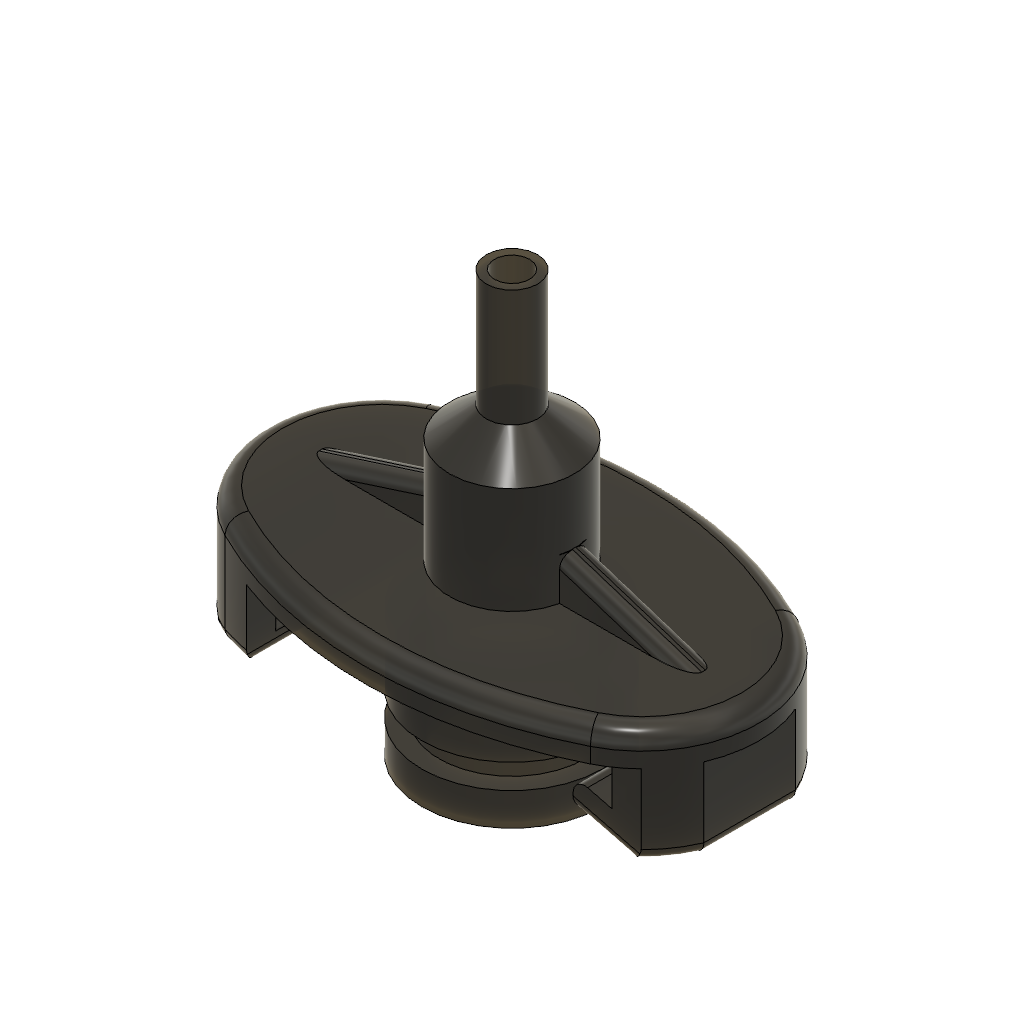
Metcal 910-3RHB (Autodesk Fusion 360 design; units mm, degrees)
Autodesk Fusion 360 part; units mm, degrees
sketch "Sketch1" plane through (0, 0, 0) normal (1, 0, 0) x (0, 0, -1)
  line L0 (7.735, 0) -> (7.735, 2.8)
  line L1 (7.735, 2.8) -> (6.235, 2.8)
  line L2 (6.235, 2.8) -> (6.235, 4.9)
  line L3 (6.235, 4.9) -> (7.735, 4.9)
  line L4 (7.735, 4.9) -> (7.735, 7.3)
  line L5 (7.735, 7.3) -> (6.25, 7.3)
  line L6 (6.25, 7.3) -> (6.25, 10.1)
  line L7 (6.25, 10.1) -> (7.7, 10.1)
  line L8 (7.7, 10.1) -> (7.7, 11.6)
  line L9 (7.735, 0) -> (5.235, 0)
  line L10 (5.235, 0) -> (5.235, 12.5)
  line L11 (5.35, 23.5) -> (5.35, 11.6)
  line L12 (5.235, 12.5) -> (1.5, 12.5)
  line L13 (1.5, 27.21503) -> (1.5, 12.5)
  line L14 (7.7, 11.6) -> (5.35, 11.6)
  line L15 (2.2, 26) -> (2.2, 36)
  line L16 (5.35, 23.5) -> (2.2, 26)
  line L17 (0, 0) -> (15.255569, 0)
  line L18 (1.5, 27.21503) -> (1.5, 36)
  line L19 (1.5, 36) -> (2.2, 36)
  dimension "d1" = 7.735
  dimension "d2" = 2.8
  dimension "d3" = 2.4
  dimension "d4" = 2.1
  dimension "d5" = 1.5
  dimension "d6" = 1.5
  dimension "d7" = 6.25
  dimension "d8" = 2.8
  dimension "d9" = 1.5
  dimension "d10" = 7.7
  dimension "d11" = 2.5
  dimension "d12" = 12.5
  dimension "d13" = 5.35
  dimension "d14" = 23.5
  dimension "d16" = 1.5
  dimension "d17" = 2.2
  dimension "d18" = 2.5
  dimension "d19" = 10
  constraint vertical L0
  constraint perpendicular L0 L1
  constraint perpendicular L1 L2
  constraint perpendicular L2 L3
  constraint perpendicular L3 L4
  constraint perpendicular L4 L5
  constraint perpendicular L5 L6
  constraint perpendicular L6 L7
  constraint perpendicular L7 L8
  constraint perpendicular L0 L9
  constraint perpendicular L9 L10
  constraint vertical L11
  constraint perpendicular L10 L12
  constraint vertical L13
  constraint perpendicular L11 L14
  constraint coincident L17.start origin
  constraint horizontal L17
  constraint coincident L9.end L17
  constraint parallel L15 L18
  constraint perpendicular L15 L19
  measures "d1" distance of L17.start L0
  measures "d2" distance of L0.start L0.end
  measures "d3" distance of L3.end L4.end
  measures "d4" distance of L1.end L2.end
  measures "d5" distance of L2.end L3.end
  measures "d6" distance of L0.end L1.end
  measures "d7" distance of L17.start L6
  measures "d8" distance of L5.end L6.end
  measures "d9" distance of L7.end L8.end
  measures "d10" distance of L17.start L8
  measures "d11" distance of L0.start L9.end
  measures "d12" distance of L9.end L10.end
  measures "d13" distance of L17.start L11
  measures "d14" vertical distance of L17.start L11.start
  measures "d16" distance of L17.start L13
  measures "d17" distance of L17.start L15
  measures "d18" vertical distance of L11.start L15.start
  measures "d19" distance of L15.end L15.start
revolve "Revolve1" add sketch "Sketch1" angle 360 about axis through (0, 1.75, 0) along (0, 1, 0) contours L0 L1 L2 L3 L4 L5 L6 L7 L8 L9 L10 L11 L12 L13 L14 L15 L16 L17 L18 L19 picked at (4.028333, 16.166667)
sketch "Sketch2" plane through (0, 11.6, 0) normal (0, 1, 0) x (-1, 0, 0)
  circle A0 centre (0, 0) radius 5.35
  circle A1 centre (0, 0) radius 7.7
  line L0 (21.15, 12.65) -> (-21.15, 12.65)
  line L1 (-21.15, 12.65) -> (-21.15, -12.65)
  line L2 (-21.15, -12.65) -> (21.15, -12.65)
  line L3 (21.15, -12.65) -> (21.15, 12.65)
  line L4 (21.15, 12.65) -> (-21.15, -12.65) construction
  line L5 (-21.15, 12.65) -> (21.15, -12.65) construction
  line L6 (0, 0) -> (7, -2.024022) construction
  line L7 (0, 0) -> (25.666571, 0) construction
  line L8 (0, 0) -> (0, -21) construction
  arc A2 (15.64922, 8.930679) -> (-15.64922, 8.930679) centre (0, -22.132075) ccw
  arc A3 (3.749439, 6.725452) -> (3.749439, -6.725452) centre (11.15, 0) ccw
  arc A4 (15.249711, -9.120985) -> (15.249711, 9.120985) centre (11.15, 0) ccw
  arc A5 (-15.249711, 9.120985) -> (-15.249711, -9.120985) centre (-11.15, 0) ccw
  arc A6 (-3.749439, -6.725452) -> (-3.749439, 6.725452) centre (-11.15, 0) ccw
  arc A7 (-15.64922, -8.930679) -> (15.64922, -8.930679) centre (0, 22.132075) ccw
  arc A8 (26.832145, 0) -> (-21.15, -5.480789) centre (0, 22.132075) ccw
  circle A9 centre (0, 0) radius 5.35
  dimension "d21" = 42.3
  dimension "d22" = 25.3
  dimension "d23" = 20
  dimension "d24" = 20
  constraint horizontal L0
  constraint perpendicular L0 L1
  constraint parallel L0 L2
  constraint parallel L1 L3
  constraint coincident L4 A0.centre
  constraint coincident L5 A0.centre
  constraint coincident A0.centre A1.centre
  constraint tangent L3 A3
  constraint tangent L1 A5
  constraint tangent L0 A2
  constraint horizontal L7
  constraint coincident A5.centre L7
  constraint coincident A3.centre L7
  constraint perpendicular L2 L8
  constraint tangent A2 A5
  constraint tangent L2 A7
  constraint tangent A3 A7
  constraint concentric A3 A4
  constraint concentric A5 A6
  constraint concentric A7 A8
  measures "d21" distance of L1.end L2.end
  measures "d22" distance of L0.end L1.end
  measures "d23" diameter of A3
  measures "d24" diameter of A5
extrude "Extrude1" add sketch "Sketch2" along normal blind 2.8 contours A0 A1 A3 A9 | A0 A1 A3 A6 A9 | A0 A1 A3 A6 A9 | A0 A1 A6 A9 | A2 A4 A5 A7 picked at (3.620764, 5.569388) picked at (2.057294, 6.01852) picked at (2.057294, -6.01852) picked at (-3.652504, 5.546347) picked at (-11.599518, 7.380524)
fillet "Fillet1" radius 1.5 4 edges at (0, 14.4, 12.65) (21.15, 14.4, 0) (0, 14.4, -12.65) (-21.15, 14.4, 0)
sketch "Sketch3" plane through (0, 11.6, 0) normal (0, -1, 0) x (1, 0, 0)
  arc A0 (-15.64922, -8.930679) -> (15.64922, -8.930679) centre (0, 22.132075) ccw
  arc A1 (15.64922, -8.930679) -> (15.64922, 8.930679) centre (11.15, 0) ccw
  arc A2 (15.64922, 8.930679) -> (-15.64922, 8.930679) centre (0, -22.132075) ccw
  arc A3 (-15.64922, 8.930679) -> (-15.64922, -8.930679) centre (-11.15, 0) ccw
  circle A4 centre (0, 0) radius 7.7
  arc A5 (15.64922, -8.930679) -> (15.64922, 8.930679) centre (11.15, 0) ccw
  line L0 (-20.35, -10) -> (-20.35, 9)
  line L1 (-21.15, -7.517399) -> (-21.15, 8.524879) construction
  line L2 (0, 0) -> (0, 5.345906) construction
  line L3 (20.35, -10) -> (20.35, 9)
  line L4 (-23, -7.116383) -> (-12.35, -7.116383)
  line L5 (20.846467, 7.116383) -> (12.35, 7.116383)
  line L6 (12.35, -10.383617) -> (12.35, 7.116383)
  line L7 (-12.35, -11.393771) -> (-12.35, -10.383617)
  line L8 (-12.35, -7.116383) -> (-12.35, 10.383617)
  dimension "d30" = 0.8
  dimension "d31" = 8
  dimension "d32" = 17.5
  dimension "d33" = 17.5
  constraint vertical L0
  constraint vertical L1
  constraint tangent A3 L1
  constraint parallel L0 L7
  constraint coincident A4.centre L2.start
  constraint vertical L2
  constraint symmetric L0.start L2 L3.start
  constraint symmetric L0.end L2 L3.end
  constraint perpendicular L4 L7
  constraint perpendicular L5 L6
  constraint collinear L7 L8
  measures "d30" distance of L0 L1
  measures "d31" distance of L0 L7
extrude "Extrude2" add sketch "Sketch3" along normal blind 7 contours A2 A3 L0 L4 L8 | A0 A1 A5 L3 L5 L6 picked at (-17.683333, -2.372128) picked at (17.683333, 2.372128)
sketch "Sketch4" plane through (0, 0, 7.116383) normal (0, 0, 1) x (1, 0, 0)
  line L0 (18.175461, 11.6) -> (12.35, 11.6)
  line L1 (12.35, 11.6) -> (12.35, 4.6)
  line L2 (12.35, 4.6) -> (18.175461, 4.6)
  line L3 (18.175461, 4.6) -> (18.175461, 11.6)
  line L4 (18.175461, 11.6) -> (18.175461, 4.6)
  line L5 (15.675461, 11.6) -> (15.675461, 7.384167)
  line L6 (15.675461, 7.384167) -> (12.052896, 8.3)
  line L7 (12.052896, 8.3) -> (12.052896, 11.6)
  line L8 (12.052896, 11.6) -> (15.675461, 11.6)
  line L9 (10.910962, 6.01004) -> (15.127758, 4.943977)
  line L10 (15.127758, 4.943977) -> (20.897603, 3.485282)
  line L11 (18.175461, 4.6) -> (18.175461, 2.814724)
  line L12 (12.052896, 8.3) -> (12.052896, 3.962226)
  line L13 (12.052896, 3.962226) -> (22.257275, 4.001156)
  dimension "d36" = 2.5
  dimension "d37" = 3.3
  dimension "d38" = 2.5
  constraint perpendicular L0 L5
  constraint parallel L1 L7
  constraint horizontal L8
  constraint parallel L6 L9
  constraint parallel L9 L10
  constraint perpendicular L2 L11
  constraint parallel L7 L12
  measures "d36" distance of L4 L5
  measures "d38" distance of L6 L9
extrude "Extrude3" cut sketch "Sketch4" against normal blind 15 contours L0 L1 L5 L6 L8 picked at (14.566974, 9.069685)
extrude "Extrude4" cut sketch "Sketch4" against normal blind 32 contours L1 L2 L9 L10 L11 L12 L13 | L1 L2 L9 L10 picked at (15.572237, 4.182603) picked at (13.275919, 5.063403)
sketch "Sketch6" plane through (0, 0, -7.116383) normal (0, 0, -1) x (-1, 0, 0)
  line L0 (18.175461, 11.6) -> (12.35, 11.6)
  line L1 (12.35, 11.6) -> (12.35, 4.6)
  line L2 (12.35, 4.6) -> (18.175461, 4.6)
  line L3 (18.175461, 4.6) -> (18.175461, 11.6)
  line L4 (12.35, 4.6) -> (18.175461, 4.6)
  line L5 (18.175461, 11.6) -> (18.175461, 4.6)
  line L6 (12.052896, 11.6) -> (15.675461, 11.6)
  line L7 (12.052896, 8.3) -> (12.052896, 11.6)
  line L8 (12.052896, 3.962226) -> (22.257275, 4.001156)
  line L9 (18.175461, 4.6) -> (18.175461, 2.814724)
  line L10 (12.052896, 8.3) -> (12.052896, 3.962226)
  line L11 (15.675461, 11.6) -> (15.675461, 7.384167)
  line L12 (18.175461, 4.6) -> (18.175461, 11.6)
  line L13 (15.127758, 4.943977) -> (20.897603, 3.485282)
  line L14 (15.675461, 7.384167) -> (12.052896, 8.3)
  line L15 (18.175461, 11.6) -> (12.35, 11.6)
  line L16 (12.35, 11.6) -> (12.35, 4.6)
  line L17 (10.910962, 6.01004) -> (15.127758, 4.943977)
  line L18 (18.175461, 11.6) -> (18.175461, 4.6)
  dimension "d43" = 2.5
  dimension "d44" = 3.3
  dimension "d45" = 2.5
  constraint perpendicular L11 L15
  constraint parallel L7 L16
  constraint horizontal L6
  constraint parallel L14 L17
  constraint parallel L13 L17
  constraint perpendicular L4 L9
  constraint parallel L7 L10
  measures "d43" distance of L5 L11
  measures "d45" distance of L14 L17
extrude "Extrude5" cut sketch "Sketch6" against normal blind 15 contours L0 L1 L6 L11 L14 L15 L16 | L1 L6 L7 L14 L16 picked at (14.566974, 9.069685) picked at (12.250965, 9.374963)
extrude "Extrude6" cut sketch "Sketch6" against normal blind 41 contours L1 L2 L4 L8 L9 L10 L13 L16 L17 | L1 L2 L4 L13 L16 L17 picked at (15.572237, 4.182603) picked at (13.275919, 5.063403)
fillet "Fillet2" radius 1 17 edges at (20.35, 4.6, 0) (-20.35, 4.6, 0) (14.419177, 5.123116, 7.116383) (19.418731, 4.6, 5.623885) (18.764877, 4.6, -6.481794) (16.074513, 4.704625, -8.7034) (14.018446, 5.224426, -9.69992) (12.35, 5.646232, -1.633617) (-12.35, 5.646232, 1.633617) (-18.764877, 4.6, 6.481794) (-16.074513, 4.704625, 8.7034) (-14.018446, 5.224426, 9.69992) (-14.419177, 5.123116, -7.116383) (-19.418731, 4.6, -5.623885) (-17.331908, 4.6, -7.116383) (-12.35, 8.224888, 0.383617) (12.35, 8.224888, -0.383617)
sketch "Sketch7" plane through (0, 14.4, 0) normal (0, 1, 0) x (-1, 0, 0)
  circle A0 centre (0, 0) radius 5.35
  arc A1 (14.974337, 7.591077) -> (-14.974337, 7.591077) centre (0, -22.132075) ccw
  arc A2 (-14.974337, 7.591077) -> (-14.974337, -7.591077) centre (-11.15, 0) ccw
  arc A3 (-14.974337, -7.591077) -> (14.974337, -7.591077) centre (0, 22.132075) ccw
  arc A4 (14.974337, -7.591077) -> (14.974337, 7.591077) centre (11.15, 0) ccw
  circle A5 centre (0, 0) radius 5.35
  line L0 (-16.4, 1.15) -> (16.4, 1.15)
  line L1 (16.4, 1.15) -> (16.4, -1.15)
  line L2 (16.4, -1.15) -> (-16.4, -1.15)
  line L3 (-16.4, -1.15) -> (-16.4, 1.15)
  line L4 (-16.4, 1.15) -> (16.4, -1.15) construction
  line L5 (16.4, 1.15) -> (-16.4, -1.15) construction
  dimension "d52" = 32.8
  dimension "d53" = 2.3
  constraint horizontal L0
  constraint perpendicular L0 L1
  constraint parallel L0 L2
  constraint parallel L1 L3
  constraint coincident L4 A0.centre
  constraint coincident L5 A0.centre
  constraint coincident A0.centre A5.centre
  measures "d52" distance of L1.end L2.end
  measures "d53" distance of L0 L2
extrude "Extrude7" add sketch "Sketch7" along normal blind 3.6 contours A0 A5 L0 L1 L2 | A0 A5 L0 L2 L3 picked at (12.716667, 0) picked at (-12.712019, 0.128671)
sketch "Sketch8" plane through (0, 0, 1.15) normal (0, 0, 1) x (1, 0, 0)
  line L0 (-16.4, 14.4) -> (-5.22494, 14.4)
  line L1 (-5.22494, 14.4) -> (-5.22494, 18)
  line L2 (-5.22494, 18) -> (-16.4, 18)
  line L3 (-16.4, 18) -> (-16.4, 14.4)
  line L4 (5.22494, 14.4) -> (16.4, 14.4)
  line L5 (16.4, 14.4) -> (16.4, 18)
  line L6 (16.4, 18) -> (5.22494, 18)
  line L7 (5.22494, 18) -> (5.22494, 14.4)
  line L8 (-16.4, 14.4) -> (-5.22494, 18)
  line L9 (5.22494, 18) -> (16.4, 14.4)
  constraint coincident L0.start L3.end
  constraint coincident L4.end L5.start
extrude "Extrude8" cut sketch "Sketch8" against normal blind 9 contours L2 L3 L8 | L5 L6 L9 picked at (-12.67498, 16.8) picked at (12.67498, 16.8)
fillet "Fillet3" radius 1 4 edges at (-10.81247, 16.2, 1.15) (-10.81247, 16.2, -1.15) (10.81247, 16.2, 1.15) (10.81247, 16.2, -1.15)
equation "d1 = ( 15.47 / 2 ) * 1 mm"
equation "d6 = d5"
equation "d7 = ( 12.5 / 2 ) * 1 mm"
equation "d10 = ( 15.4 / 2 ) * 1 mm"
equation "d13 = ( 10.7 / 2 ) * 1 mm"
equation "d17 = ( 4.4 / 2 ) * 1 mm"
